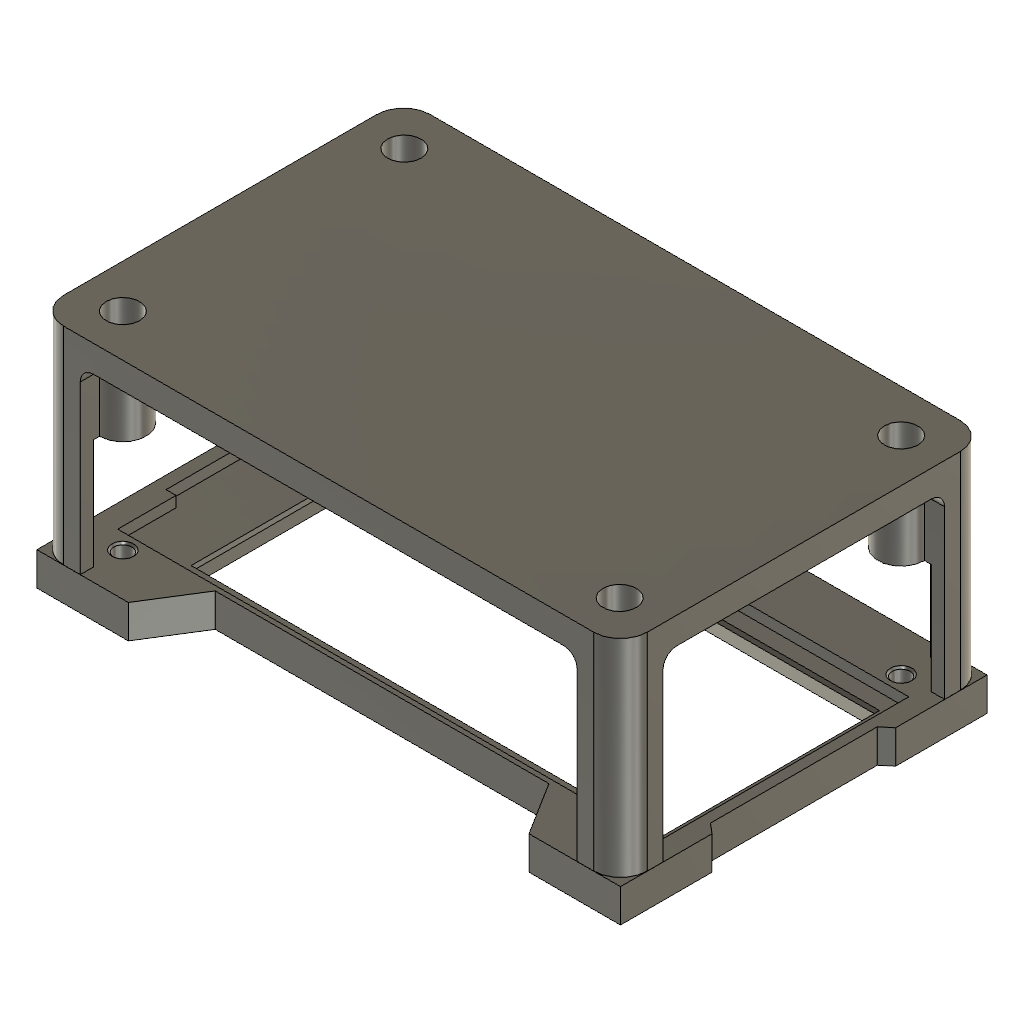
poma-screen-mount (Autodesk Fusion 360 design; units mm, degrees)
part number: 2026-09-07-19-10-37-446
Autodesk Fusion 360 part; units mm, degrees
sketch "Sketch1" plane through (0, 0, 0) normal (0, 0, 1) x (1, 0, 0)
  line L0 (37.211, 21.082) -> (-37.211, 21.082) construction
  line L1 (-37.211, 21.082) -> (-37.211, -21.082) construction
  line L2 (-37.211, -21.082) -> (37.211, -21.082) construction
  line L3 (37.211, -21.082) -> (37.211, 21.082) construction
  line L4 (37.211, 21.082) -> (-37.211, -21.082) construction
  line L5 (-37.211, 21.082) -> (37.211, -21.082) construction
  line L6 (39.751, 23.495) -> (-39.751, 23.495) construction
  line L7 (-39.751, 23.495) -> (-39.751, -23.495) construction
  line L8 (-39.751, -23.495) -> (39.751, -23.495) construction
  line L9 (39.751, -23.495) -> (39.751, 23.495) construction
  line L10 (39.751, 23.495) -> (-39.751, -23.495) construction
  line L11 (-39.751, 23.495) -> (39.751, -23.495) construction
  line L12 (40.5448, -24.2888) -> (40.5448, 24.2888)
  line L13 (40.5448, 24.2888) -> (-40.5448, 24.2888)
  line L14 (-40.5448, 24.2888) -> (-40.5448, -24.2888)
  line L15 (-40.5448, -24.2888) -> (40.5448, -24.2888)
  line L16 (-43.7197, -27.4638) -> (43.7197, -27.4638)
  line L17 (43.7197, -27.4638) -> (43.7197, 27.4638)
  line L18 (43.7197, 27.4638) -> (-43.7197, 27.4638)
  line L19 (-43.7197, 27.4638) -> (-43.7197, -27.4638)
  line L20 (-40.5448, 9.525) -> (-41.9163, 9.525)
  line L21 (-41.9163, 9.525) -> (-41.9163, -9.525)
  line L22 (-41.9163, -9.525) -> (-40.5447, -9.525)
  dimension "d1" = 74.422
  dimension "d2" = 42.164
  dimension "d3" = 79.502
  dimension "d4" = 46.99
  dimension "d5" = 0.7937
  dimension "d6" = 3.175
  dimension "d7" = 1.3716
  dimension "d8" = 19.05
  dimension "d9" = 9.525
  constraint horizontal L0
  constraint perpendicular L0 L1
  constraint parallel L0 L2
  constraint parallel L1 L3
  constraint coincident L4 origin
  constraint coincident L5 origin
  constraint horizontal L6
  constraint perpendicular L6 L7
  constraint parallel L6 L8
  constraint parallel L7 L9
  constraint coincident L10 origin
  constraint coincident L11 origin
  constraint coincident L14 L20.start
  constraint perpendicular L14 L20
  constraint perpendicular L20 L21
  constraint perpendicular L14 L22
  measures "d1" distance of L1.end L2.end
  measures "d2" distance of L0.end L1.end
  measures "d3" distance of L7.end L8.end
  measures "d4" distance of L6.end L7.end
  measures "d7" distance of L20.start L20.end
  measures "d8" distance of L20.end L21.end
  measures "d9" distance of origin L20
extrude "Extrude1" add sketch "Sketch1" against normal blind 5 contours L12 L13 L14 L15 | L14 L20 L21 L22 | L16 L17 L18 L19 makes body 1
sketch "Sketch2" plane through (0, 0, 0) normal (0, 0, 1) x (-1, 0, 0)
  line L0 (-39.6875, -19.05) -> (39.6875, -19.05) construction
  line L1 (39.6875, -19.05) -> (39.6875, 19.05) construction
  line L2 (39.6875, 19.05) -> (-39.6875, 19.05) construction
  line L3 (-39.6875, 19.05) -> (-39.6875, -19.05) construction
  line L4 (-39.6875, -19.05) -> (39.6875, 19.05) construction
  line L5 (39.6875, -19.05) -> (-39.6875, 19.05) construction
  line L6 (31.1875, -15.875) -> (-38.1875, -15.875)
  line L7 (-38.1875, -15.875) -> (-38.1875, 15.875)
  line L8 (-38.1875, 15.875) -> (31.1875, 15.875)
  line L9 (31.1875, 15.875) -> (31.1875, -15.875)
  line L10 (-38.1875, 0) -> (-39.6875, 0) construction
  line L11 (43.7197, -27.4638) -> (43.7197, 27.4638)
  line L12 (43.7197, 27.4638) -> (-43.7197, 27.4638)
  line L13 (-43.7197, 27.4638) -> (-43.7197, -27.4638)
  line L14 (-43.7197, -27.4638) -> (43.7197, -27.4638)
  dimension "d20" = 79.375
  dimension "d21" = 38.1
  dimension "d22" = 31.75
  dimension "d23" = 8.5
  dimension "d24" = 1.5
  constraint horizontal L0
  constraint perpendicular L0 L1
  constraint parallel L0 L2
  constraint parallel L1 L3
  constraint coincident L4 origin
  constraint coincident L5 origin
  constraint horizontal L6
  constraint vertical L7
  constraint horizontal L8
  constraint vertical L9
  constraint midpoint L7 L10.start
  constraint midpoint L3 L10.end
  constraint horizontal L10
  measures "d20" distance of L1.end L2.end
  measures "d21" distance of L0.end L1.end
  measures "d22" distance of L6.end L7.end
  measures "d23" distance of L1 L9
  measures "d24" distance of L3 L7
extrude "Extrude3" cut sketch "Sketch2" against normal through all contours L6 L7 L8 L9 bodies 1
sketch "Sketch3" plane through (0, 0, 0) normal (0, 0, 1) x (1, 0, 0)
  line L0 (-30, -27.4637) -> (-25, -19.4637)
  line L1 (-25, -19.4637) -> (25, -19.4638)
  line L2 (25, -19.4638) -> (30, -27.4638)
  line L3 (0, -19.4637) -> (0, 0) construction
  line L4 (-30, -27.4637) -> (30, -27.4638) construction
  line L5 (30, -27.4638) -> (-30, -27.4637)
  line L6 (0, -27.4637) -> (0, -19.4637) construction
  line L7 (43.7197, -13.75) -> (43.7197, 13.75)
  line L8 (43.7197, 13.75) -> (42.2197, 12.5)
  line L9 (42.2197, 12.5) -> (42.2197, -12.5)
  line L10 (42.2197, -12.5) -> (43.7198, -13.75)
  line L11 (42.2197, 0) -> (43.7198, 0) construction
  point P0 (43.7197, -27.4638)
  dimension "d30" = 8
  dimension "d31" = 50
  dimension "d32" = 5
  dimension "d53" = 1.5
  dimension "d54" = 1.25
  dimension "d55" = 25
  constraint midpoint L1 L3.start
  constraint coincident L3.end origin
  constraint vertical L3
  constraint midpoint L5 L6.start
  constraint vertical L6
  constraint horizontal L1
  constraint horizontal L5
  constraint coincident L5 P0
  constraint vertical L7
  constraint parallel L7 L9
  constraint midpoint L9 L11.start
  constraint horizontal L11
  constraint coincident L3.end L11
  constraint coincident P0 L7
  measures "d30" distance of L3.start L6.start
  measures "d31" distance of L0.end L1.end
  measures "d32" horizontal distance of L0.start L0.end
  measures "d54" vertical distance of L7.end L8.end
  measures "d55" distance of L8.end L9.end
extrude "Extrude4" cut sketch "Sketch3" along normal through all and the other way through all bodies 1
hole "Hole1" at (-37.211, 21.082, 0) at (-37.211, -21.082, 0) at (37.211, 21.082, 0) at (37.211, -21.082, 0) direction (0, 0, -1) diameter 2.7 depth 4.5 tip angle 180 countersink diameter 3.25 countersink angle 90 bodies 1
sketch "Sketch5" plane through (0, 0, 0) normal (0, 0, 1) x (-1, 0, 0)
  line L0 (31.1875, 15.875) -> (31.1875, -15.875)
  line L1 (31.1875, -15.875) -> (-38.1875, -15.875)
  line L2 (-38.1875, -15.875) -> (-38.1875, 15.875)
  line L3 (-38.1875, 15.875) -> (31.1875, 15.875)
  line L4 (-43.7197, 27.4638) -> (-43.7197, 13.75)
  line L5 (-43.7197, -27.4638) -> (43.7197, -27.4638)
  line L6 (43.7197, -27.4638) -> (43.7197, 27.4638)
  line L7 (-30, 27.4638) -> (-43.7197, 27.4638)
  line L8 (30, 27.4637) -> (25, 19.4637)
  line L9 (25, 19.4637) -> (-25, 19.4638)
  line L10 (-25, 19.4638) -> (-30, 27.4638)
  line L11 (-42.2197, 12.5) -> (-42.2197, -12.5)
  circle A0 centre (-37.211, 21.082) radius 1.625
  circle A1 centre (37.211, 21.082) radius 1.625
  circle A2 centre (37.211, -21.082) radius 1.625
  circle A3 centre (-37.211, -21.082) radius 1.625
  line L12 (40.3125, -18.75) -> (-40.6875, -18.75)
  line L13 (-40.6875, -18.75) -> (-40.6875, 18.75)
  line L14 (-40.6875, 18.75) -> (40.3125, 18.75)
  line L15 (40.3125, 18.75) -> (40.3125, -18.75)
  line L16 (-40.6875, 0) -> (0, 0) construction
  line L17 (40.3125, -10) -> (41.8125, -10)
  line L18 (41.8125, -10) -> (41.8125, 10)
  line L19 (41.8125, 10) -> (40.3125, 10)
  line L20 (40.3125, 10) -> (40.3125, -10)
  line L21 (-43.7197, 13.75) -> (-42.2197, 12.5)
  line L22 (-42.2197, -12.5) -> (-43.7198, -13.75)
  line L23 (-43.7197, -13.75) -> (-43.7197, -27.4638)
  line L24 (43.7197, 27.4638) -> (30, 27.4637)
  dimension "d56" = 37.5
  dimension "d57" = 81
  dimension "d58" = 2.5
  dimension "d73" = 20
  dimension "d74" = 1.5
  dimension "d75" = 10
  constraint horizontal L12
  constraint vertical L13
  constraint horizontal L14
  constraint vertical L15
  constraint midpoint L13 L16.start
  constraint coincident L16.end origin
  constraint horizontal L16
  constraint horizontal L17
  constraint vertical L18
  constraint horizontal L19
  constraint vertical L20
  constraint coincident L12.start L20
  measures "d56" distance of L12.end L13.end
  measures "d57" distance of L12.start L12.end
  measures "d58" distance of L2 L13
  measures "d73" distance of L17.end L18.end
  measures "d74" distance of L17.start L17.end
  measures "d75" distance of L16.end L17
extrude "Extrude6" cut sketch "Sketch5" against normal blind 1.6 contours L12 L13 L14 L15 L20 | L15 L17 L18 L19 L20 bodies 1
draft "Draft1" angle -20 neutral plane through (0, 0, -1.6) pull (0, 0, 1) 4 faces at (-31.1875, -5.2917, -3.8667) (-8.0625, 15.875, -2.7333) (15.0625, -15.875, -2.7333) (38.1875, 5.2917, -3.8667) on bodies 1
chamfer "Chamfer1" distance 0.5 angle 45 4 edges at (-31.1875, 0, -1.6) (3.5, 15.875, -1.6) (3.5, -15.875, -1.6) (38.1875, 0, -1.6) tangent chain off on bodies 1
ref_plane "WorkPlane4" through (0, 0, 27) normal (0, 0, 1) x (1, 0, 0)
sketch "Sketch12" plane through (0, 0, 27) normal (0, 0, 1) x (1, 0, 0)
  line L0 (-43.7197, 27.4638) -> (-43.7197, -27.4638)
  line L1 (43.7197, 27.4638) -> (-43.7197, 27.4638)
  line L2 (43.7197, -27.4638) -> (43.7197, 27.4638)
  line L3 (-43.7197, -27.4638) -> (43.7197, -27.4638)
extrude "Extrude9" add sketch "Sketch12" along normal blind 4 separate body makes body 2
ref_plane "WorkPlane5" through (0, 0, 16.5) normal (0, 0, 1) x (1, 0, 0)
sketch "Sketch15" plane through (0, 0, 16.5) normal (0, 0, 1) x (1, 0, 0)
  circle A0 centre (-37.211, 21.082) radius 3.5
  circle A1 centre (37.211, 21.082) radius 3.5
  circle A2 centre (37.211, -21.082) radius 3.5
  circle A3 centre (-37.211, -21.082) radius 3.5
  circle A4 centre (37.211, 21.082) radius 1.25
  circle A5 centre (-37.211, 21.082) radius 1.25
  circle A6 centre (-37.211, -21.082) radius 1.25
  circle A7 centre (37.211, -21.082) radius 1.25
  line L0 (43.7197, -27.4638) -> (-43.7197, -27.4638)
  line L1 (-43.7197, -27.4638) -> (-43.7197, 27.4638)
  line L2 (-43.7197, 27.4638) -> (43.7197, 27.4638)
  line L3 (43.7197, 27.4638) -> (43.7197, -27.4638)
  line L4 (37.211, 21.082) -> (37.211, 27.4638)
  line L5 (37.211, 21.082) -> (43.7197, 21.082)
  line L6 (37.211, -21.082) -> (43.7197, -21.082)
  line L7 (37.211, -21.082) -> (37.211, -27.4638)
  line L8 (-37.211, -21.082) -> (-43.7197, -21.082)
  line L9 (-43.7197, -21.082) -> (-37.211, -21.082)
  line L10 (-37.211, -27.4638) -> (-37.211, -21.082)
  line L11 (-37.211, 21.082) -> (-37.211, 27.4638)
  line L12 (-37.211, 21.082) -> (-43.7197, 21.082)
  line L13 (41.7197, 21.082) -> (41.7197, 25.4638)
  line L14 (41.7197, 25.4638) -> (37.211, 25.4638)
  line L15 (-37.211, 25.4638) -> (-41.7197, 25.4638)
  line L16 (-41.7197, 25.4638) -> (-41.7197, 21.082)
  line L17 (-41.7197, -21.082) -> (-41.7197, -25.4638)
  line L18 (-41.7197, -25.4638) -> (-37.211, -25.4638)
  line L19 (37.211, -25.4638) -> (41.7197, -25.4638)
  line L20 (41.7197, -25.4638) -> (41.7197, -21.082)
  point P0 (-37.211, 21.082)
  point P1 (37.211, 21.082)
  point P2 (37.211, -21.082)
  point P3 (-37.211, -21.082)
  dimension "d128" = 7
  dimension "d129" = 7
  dimension "d130" = 7
  dimension "d131" = 7
  dimension "d132" = 2.5
  dimension "d133" = 2.5
  dimension "d134" = 2.5
  dimension "d135" = 2.5
  dimension "d167" = 2
  dimension "d168" = 2
  dimension "d169" = 2
  dimension "d170" = 2
  dimension "d171" = 2
  dimension "d172" = 2
  dimension "d173" = 2
  dimension "d174" = 2
  constraint coincident P0 A0.centre
  constraint coincident P1 A1.centre
  constraint coincident P2 A2.centre
  constraint coincident P3 A3.centre
  constraint concentric A0 A5
  constraint concentric A3 A6
  constraint concentric A2 A7
  constraint coincident L2 L4.end
  constraint perpendicular L2 L4
  constraint coincident L3 L5.end
  constraint perpendicular L3 L5
  constraint coincident L3 L6.end
  constraint perpendicular L3 L6
  constraint coincident L0 L7.end
  constraint perpendicular L0 L7
  constraint coincident L1 L8.end
  constraint perpendicular L1 L8
  constraint coincident L0 L10.start
  constraint perpendicular L8 L10
  constraint coincident L2 L11.end
  constraint perpendicular L2 L11
  constraint coincident L1 L12.end
  constraint perpendicular L1 L12
  constraint coincident L5 L13.start
  constraint perpendicular L5 L13
  constraint coincident L4 L14.end
  constraint perpendicular L4 L14
  constraint coincident L11 L15.start
  constraint perpendicular L11 L15
  constraint coincident L12 L16.end
  constraint perpendicular L12 L16
  constraint coincident L9 L17.start
  constraint perpendicular L9 L17
  constraint coincident L10 L18.end
  constraint perpendicular L10 L18
  constraint coincident L7 L19.start
  constraint perpendicular L7 L19
  constraint coincident L6 L20.end
  constraint perpendicular L6 L20
  measures "d128" diameter of A0
  measures "d129" diameter of A1
  measures "d130" diameter of A2
  measures "d131" diameter of A3
  measures "d132" diameter of A4
  measures "d133" diameter of A5
  measures "d134" diameter of A6
  measures "d135" diameter of A7
  measures "d167" distance of L3 L13
  measures "d168" distance of L2 L14
  measures "d169" distance of L3 L20
  measures "d170" distance of L0 L19
  measures "d171" distance of L0 L18
  measures "d172" distance of L1 L17
  measures "d173" distance of L1 L16
  measures "d174" distance of L2 L15
extrude "Extrude12" add sketch "Sketch15" along normal up to surface (10.5 mm away) contours A0 A5 L11 L12 | A0 A5 L11 L12 | A0 L11 L12 L15 L16 | L1 L2 L11 L12 L15 L16 | L2 L3 L4 L5 L13 L14 | L0 L1 L8 L9 L10 L17 L18 | A1 L4 L5 L13 L14 | A3 L8 L9 L10 L17 L18 | A1 A4 L4 L5 | A1 A4 L4 L5 | A3 A6 L8 L9 L10 | A3 A6 L8 L9 L10 | L0 L3 L6 L7 L19 L20 | A2 L6 L7 L19 L20 | A2 A7 L6 L7 | A2 A7 L6 L7 bodies 2
extrude "Extrude16" add sketch "Sketch15" against normal blind 16.49 contours L1 L2 L11 L12 L15 L16 | L2 L3 L4 L5 L13 L14 | L0 L1 L8 L9 L10 L17 L18 | L0 L3 L6 L7 L19 L20 bodies 2
sketch "Sketch13" plane through (0, 0, 31) normal (0, 0, 1) x (-1, 0, 0)
  line L0 (43.7197, 27.4638) -> (-43.7197, 27.4638)
  line L1 (-43.7197, 27.4638) -> (-43.7197, -27.4638)
  line L2 (-43.7197, -27.4638) -> (43.7197, -27.4638)
  line L3 (43.7197, -27.4638) -> (43.7197, 27.4638)
  circle A0 centre (-37.211, 21.082) radius 2.5
  circle A1 centre (-37.211, -21.082) radius 2.5
  circle A2 centre (37.211, -21.082) radius 2.5
  circle A3 centre (37.211, 21.082) radius 2.5
  circle A4 centre (37.211, -21.082) radius 1.25
  circle A5 centre (-37.211, -21.082) radius 1.25
  circle A6 centre (-37.211, 21.082) radius 1.25
  circle A7 centre (37.211, 21.082) radius 1.25
  point P0 (37.211, -21.082)
  point P1 (-37.211, -21.082)
  point P2 (-37.211, 21.082)
  point P3 (37.211, 21.082)
  dimension "d105" = 5
  dimension "d106" = 5
  dimension "d107" = 5
  dimension "d108" = 5
  dimension "d109" = 2.5
  dimension "d110" = 2.5
  dimension "d111" = 2.5
  dimension "d112" = 2.5
  constraint coincident P2 A0.centre
  constraint coincident P1 A1.centre
  constraint coincident P0 A2.centre
  constraint coincident P3 A3.centre
  constraint concentric A3 A7
  measures "d105" diameter of A0
  measures "d106" diameter of A1
  measures "d107" diameter of A2
  measures "d108" diameter of A3
  measures "d109" diameter of A4
  measures "d110" diameter of A5
  measures "d111" diameter of A6
  measures "d112" diameter of A7
extrude "Extrude10" cut sketch "Sketch13" against normal blind 11.5 contours A0 | A1 | A2 | A3 | A4 | A5 | A6 | A7 bodies 2
sketch "Sketch18" plane through (0, 0, 27) normal (0, 0, -1) x (1, 0, 0)
  line L0 (40.711, -21.082) -> (43.7198, -21.082)
  line L1 (43.7197, -21.082) -> (43.7197, 21.082)
  line L2 (43.7197, 21.082) -> (40.711, 21.082)
  arc A0 (37.211, 24.582) -> (40.711, 21.082) centre (37.211, 21.082) ccw
  line L3 (37.211, 24.582) -> (37.211, 27.4638)
  line L4 (37.211, 27.4638) -> (-37.211, 27.4638)
  line L5 (-37.211, 27.4638) -> (-37.211, 24.582)
  arc A1 (-40.711, 21.082) -> (-37.211, 24.582) centre (-37.211, 21.082) ccw
  line L6 (-40.711, 21.082) -> (-43.7198, 21.082)
  line L7 (-43.7197, 21.082) -> (-43.7197, -21.082)
  line L8 (-43.7197, -21.082) -> (-40.711, -21.082)
  arc A2 (-37.211, -24.582) -> (-40.711, -21.082) centre (-37.211, -21.082) ccw
  line L9 (-37.211, -24.582) -> (-37.211, -27.4638)
  line L10 (-37.211, -27.4638) -> (37.211, -27.4638)
  line L11 (37.211, -27.4638) -> (37.211, -24.582)
  arc A3 (40.711, -21.082) -> (37.211, -24.582) centre (37.211, -21.082) ccw
  line L12 (43.7197, 18) -> (-20.2803, 18)
  line L13 (-20.2803, 18) -> (-20.2803, -18)
  line L14 (-20.2803, -18) -> (43.7197, -18)
  line L15 (43.7197, -18) -> (43.7197, 18)
  line L16 (-20.2803, 13) -> (-18.2803, 13)
  line L17 (-18.2803, 13) -> (-18.2803, 16)
  line L18 (-18.2803, 16) -> (-15.2803, 16)
  line L19 (-15.2803, 16) -> (-15.2803, 18)
  line L20 (-20.2803, -13) -> (-18.2803, -13)
  line L21 (-18.2803, -13) -> (-18.2803, -16)
  line L22 (-18.2803, -16) -> (-15.2803, -16)
  line L23 (-15.2803, -16) -> (-15.2803, -18)
  dimension "d178" = 64
  dimension "d179" = 36
  dimension "d180" = 18
  dimension "d181" = 2
  dimension "d182" = 2
  dimension "d183" = 5
  dimension "d184" = 5
  dimension "d185" = 5
  dimension "d186" = 5
  dimension "d187" = 2
  dimension "d188" = 2
  constraint horizontal L12
  constraint vertical L13
  constraint horizontal L14
  constraint vertical L15
  constraint coincident L1 L12.start
  constraint coincident L13 L16.start
  constraint perpendicular L13 L16
  constraint perpendicular L13 L18
  constraint coincident L12 L19.end
  constraint perpendicular L12 L19
  constraint coincident L13 L20.start
  constraint perpendicular L13 L20
  constraint perpendicular L20 L21
  constraint perpendicular L21 L22
  constraint coincident L14 L23.end
  constraint perpendicular L14 L23
  constraint vertical L17
  measures "d178" distance of L12.start L12.end
  measures "d179" distance of L12.start L14.end
  measures "d180" distance of origin L12
  measures "d181" distance of L18.end L19.end
  measures "d182" distance of L16.start L16.end
  measures "d183" distance of L12 L16
  measures "d184" distance of L13 L19
  measures "d185" distance of L14 L20
  measures "d186" distance of L13 L23
  measures "d187" distance of L20.start L20.end
  measures "d188" distance of L22.end L23.end
extrude "Extrude17" cut sketch "Sketch18" against normal blind 1 contours L13 L14 L20 L21 L22 L23 | L12 L13 L16 L17 L18 L19 bodies 2
sketch "Sketch19" plane through (0, 0, 27) normal (0, 0, -1) x (1, 0, 0)
  line L0 (-20.2803, 18) -> (-15.2803, 18)
  line L1 (-15.2803, 18) -> (-15.2803, 16)
  line L2 (-15.2803, 16) -> (-18.2803, 16)
  line L3 (-18.2803, 16) -> (-18.2803, 13)
  line L4 (-18.2803, 13) -> (-20.2803, 13)
  line L5 (-20.2803, 13) -> (-20.2803, 18)
  line L6 (-15.2803, -18) -> (-20.2803, -18)
  line L7 (-20.2803, -18) -> (-20.2803, -13)
  line L8 (-20.2803, -13) -> (-18.2803, -13)
  line L9 (-18.2803, -13) -> (-18.2803, -16)
  line L10 (-18.2803, -16) -> (-15.2803, -16)
  line L11 (-15.2803, -16) -> (-15.2803, -18)
  line L12 (40.711, -21.082) -> (43.7198, -21.082)
  line L13 (43.7197, -21.082) -> (43.7197, 21.082)
  line L14 (43.7197, 21.082) -> (40.711, 21.082)
  arc A0 (37.211, 24.582) -> (40.711, 21.082) centre (37.211, 21.082) ccw
  line L15 (37.211, 24.582) -> (37.211, 27.4638)
  line L16 (37.211, 27.4638) -> (-37.211, 27.4638)
  line L17 (-37.211, 27.4638) -> (-37.211, 24.582)
  arc A1 (-40.711, 21.082) -> (-37.211, 24.582) centre (-37.211, 21.082) ccw
  line L18 (-40.711, 21.082) -> (-43.7198, 21.082)
  line L19 (-43.7197, 21.082) -> (-43.7197, -21.082)
  line L20 (-43.7197, -21.082) -> (-40.711, -21.082)
  arc A2 (-37.211, -24.582) -> (-40.711, -21.082) centre (-37.211, -21.082) ccw
  line L21 (-37.211, -24.582) -> (-37.211, -27.4638)
  line L22 (-37.211, -27.4638) -> (37.211, -27.4638)
  line L23 (37.211, -27.4638) -> (37.211, -24.582)
  arc A3 (40.711, -21.082) -> (37.211, -24.582) centre (37.211, -21.082) ccw
  line L24 (-43.7197, 12.7) -> (-25.9398, 12.7)
  line L25 (-25.9398, 12.7) -> (-25.9398, -12.7)
  line L26 (-25.9398, -12.7) -> (-43.7197, -12.7)
  line L27 (-43.7197, -12.7) -> (-43.7197, 12.7)
  dimension "d191" = 17.78
  dimension "d192" = 25.4
  dimension "d193" = 12.7
  constraint horizontal L24
  constraint vertical L25
  constraint horizontal L26
  constraint vertical L27
  constraint coincident L19 L24.start
  measures "d191" distance of L24.start L24.end
  measures "d192" distance of L24.start L26.end
  measures "d193" distance of origin L24
extrude "Extrude18" add sketch "Sketch19" along normal blind 5 contours L19 L24 L25 L26 L27 bodies 2
sketch "Sketch20" plane through (0, 0, 22) normal (0, 0, -1) x (1, 0, 0)
  line L0 (-43.7197, -12.7) -> (-25.9398, -12.7)
  line L1 (-25.9398, -12.7) -> (-25.9398, 12.7)
  line L2 (-25.9398, 12.7) -> (-43.7197, 12.7)
  line L3 (-43.7197, 12.7) -> (-43.7197, -12.7)
  line L4 (-41.1797, 10.16) -> (-41.1797, -10.16)
  line L5 (-41.1797, 0) -> (0, 0) construction
  dimension "d196" = 20.32
  dimension "d197" = 2.54
  constraint vertical L4
  constraint midpoint L4 L5.start
  constraint coincident L5.end origin
  constraint horizontal L5
  measures "d196" distance of L4.start L4.end
  measures "d197" distance of L3 L4
hole "Hole3" at (-41.1797, -10.16, 22) at (-41.1797, 10.16, 22) direction (0, 0, 1) diameter 2.7 depth 5 tip angle 180 countersink diameter 3.25 countersink angle 90 bodies 2
sketch "Sketch21" plane through (0, 0, 22) normal (0, 0, -1) x (1, 0, 0)
  circle A0 centre (-41.1797, 10.16) radius 1.625
  circle A1 centre (-41.1797, -10.16) radius 1.625
  line L0 (-43.7197, -12.7) -> (-25.9398, -12.7)
  line L1 (-25.9398, -12.7) -> (-25.9398, 12.7)
  line L2 (-25.9398, 12.7) -> (-43.7197, 12.7)
  line L3 (-43.7197, 12.7) -> (-43.7197, -12.7)
  line L4 (-41.7197, 6.75) -> (-41.7197, -6.75) construction
  line L5 (-41.7197, -6.75) -> (-32.8448, -6.75) construction
  line L6 (-32.8448, -6.75) -> (-29.7197, -3.625) construction
  line L7 (-29.7197, -3.625) -> (-29.7197, 3.625) construction
  line L8 (-29.7197, 3.625) -> (-32.8448, 6.75) construction
  line L9 (-32.8448, 6.75) -> (-41.7197, 6.75) construction
  line L10 (-29.7197, 0) -> (-41.7197, 0) construction
  line L11 (-42.2197, -7.25) -> (-32.6376, -7.25)
  line L12 (-32.6376, -7.25) -> (-29.2197, -3.8321)
  line L13 (-29.2197, -3.8321) -> (-29.2197, 3.8321)
  line L14 (-29.2197, 3.8321) -> (-32.6376, 7.25)
  line L15 (-32.6376, 7.25) -> (-42.2197, 7.25)
  line L16 (-42.2197, 7.25) -> (-42.2197, -7.25)
  line L17 (-38.8197, 7.25) -> (-34.8197, 7.25)
  line L18 (-34.8197, 7.25) -> (-34.8197, 11.25)
  line L19 (-34.8197, 11.25) -> (-38.8197, 11.25)
  line L20 (-38.8197, 11.25) -> (-38.8197, 7.25)
  line L21 (-38.8197, -7.25) -> (-34.8197, -7.25)
  line L22 (-34.8197, -7.25) -> (-34.8197, -11.25)
  line L23 (-34.8197, -11.25) -> (-38.8197, -11.25)
  line L24 (-38.8197, -11.25) -> (-38.8197, -7.25)
  line L25 (-42.2197, 7.25) -> (-43.7198, 7.25)
  line L26 (-43.7197, 7.25) -> (-43.7197, -7.25)
  line L27 (-43.7197, -7.25) -> (-42.2197, -7.25)
  line L28 (-42.2197, -7.25) -> (-42.2197, 7.25)
  dimension "d215" = 14
  dimension "d216" = 13.5
  dimension "d217" = 12
  dimension "d218" = 7.25
  dimension "d219" = 0.5
  dimension "d220" = 4
  dimension "d221" = 4
  dimension "d223" = 6.9
  dimension "d224" = 4
  dimension "d225" = 4
  dimension "d226" = 6.9
  constraint vertical L4
  constraint perpendicular L4 L5
  constraint perpendicular L6 L8
  constraint horizontal L9
  constraint vertical L7
  constraint midpoint L7 L10.start
  constraint midpoint L4 L10.end
  constraint horizontal L10
  constraint coincident origin L10
  constraint vertical L5.end L8.end
  constraint horizontal L17
  constraint vertical L18
  constraint horizontal L19
  constraint vertical L20
  constraint coincident L15 L17.start
  constraint horizontal L21
  constraint vertical L22
  constraint horizontal L23
  constraint vertical L24
  constraint coincident L11.end L21
  constraint horizontal L25
  constraint vertical L26
  constraint horizontal L27
  constraint vertical L28
  constraint coincident L3 L26.end
  constraint coincident L11.start L27
  measures "d215" distance of L3 L7
  measures "d216" distance of L4.start L4.end
  measures "d217" distance of L10.start L10.end
  measures "d218" distance of L6.end L7.end
  measures "d220" distance of L21.start L21.end
  measures "d221" distance of L21.start L23.end
  measures "d223" distance of L4 L18
  measures "d224" distance of L18.end L19.end
  measures "d225" distance of L17.end L18.end
  measures "d226" distance of L4 L22
extrude "Extrude19" cut sketch "Sketch21" against normal blind 3 contours L3 L16 L25 L26 L27 L28 | L11 L12 L13 L14 L15 L16 L17 L21 L28 bodies 2
extrude "Extrude20" cut sketch "Sketch21" against normal blind 1 contours L11 L21 L22 L23 L24 | L15 L17 L18 L19 L20 bodies 2
fillet "Fillet10" radius 4 4 edges at (43.7197, 27.4638, 15.505) (-43.7197, 27.4638, 15.505) (-43.7197, -27.4638, 15.505) (43.7197, -27.4638, 15.505) on bodies 2
fillet "Fillet11" radius 2 18 edges at (41.7197, 25.4638, 8.255) (41.7197, -25.4638, 8.255) (-41.7197, -25.4638, 8.255) (-41.7197, 25.4638, 8.255) (-34.7361, 18.6071, 27) (-37.211, 26.0229, 27) (-34.7361, -18.6071, 27) (-37.211, -26.0229, 27) (42.2154, 21.082, 27) (34.7361, 18.6071, 27) (42.2154, -21.082, 27) (34.7361, -18.6071, 27) (37.211, 26.0229, 27) (37.211, -26.0229, 27) (-42.2154, -21.082, 27) (-42.2154, 21.082, 27) (-25.9398, 12.7, 24.5) (-25.9398, -12.7, 24.5) on bodies 2
equation "d5 = ( 0.125 / 4 ) * 1 in"
equation "d9 = ( 0.75 / 2 ) * 1 in"
equation "d47 = 3 mm * 0.9"
equation "d180 = ( 36 / 2 ) * 1 mm"
equation "d193 = 1 in / 2"
equation "d199 = ( 3 * 0.9 ) * 1 mm"
